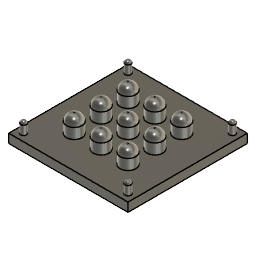
RUN 6 HOLLOW MAKER (Autodesk Fusion 360 design; units mm, degrees)
Autodesk Fusion 360 part; units mm, degrees
sketch "Sketch1" plane through (0, 0, 0) normal (0, 0, 1) x (1, 0, 0)
  line L0 (15, 15) -> (-15, 15)
  line L1 (-15, 15) -> (-15, -15)
  line L2 (-15, -15) -> (15, -15)
  line L3 (15, -15) -> (15, 15)
  line L4 (15, 15) -> (-15, -15) construction
  line L5 (-15, 15) -> (15, -15) construction
  line L6 (-20, 20) -> (-20, -20)
  line L7 (-20, -20) -> (20, -20)
  line L8 (20, -20) -> (20, 20)
  line L9 (20, 20) -> (-20, 20)
  circle A0 centre (0, 0) radius 2.625
  circle A1 centre (-9, -9) radius 2.625
  circle A2 centre (0, -9) radius 2.625
  circle A3 centre (9, -9) radius 2.625
  circle A4 centre (-9, 0) radius 2.625
  circle A5 centre (9, 0) radius 2.625
  circle A6 centre (-9, 9) radius 2.625
  circle A7 centre (0, 9) radius 2.625
  circle A8 centre (9, 9) radius 2.625
  line L10 (15, -15) -> (20, -20)
  line L11 (15, 15) -> (20, 20)
  line L12 (-15, 15) -> (-20, 20)
  line L13 (-15, -15) -> (-20, -20)
  circle A9 centre (-17.5, -17.5) radius 1
  circle A10 centre (17.5, -17.5) radius 1
  circle A11 centre (-17.5, 17.5) radius 1
  circle A12 centre (17.5, 17.5) radius 1
  dimension "d1" = 30
  dimension "d2" = 30
  dimension "d3" = 5
  dimension "d4" = 5.25
  dimension "d7" = 9
  dimension "d8" = 9
  dimension "d15" = 2
  dimension "d18" = 35
  dimension "d19" = 35
  constraint horizontal L0
  constraint perpendicular L0 L1
  constraint parallel L0 L2
  constraint parallel L1 L3
  constraint coincident L4 A0.centre
  constraint coincident L5 A0.centre
  constraint coincident A0.centre origin
  constraint perpendicular L10 L11
  constraint perpendicular L12 L13
  constraint midpoint L13 A9.centre
  measures "d1" distance of L1.end L2.end
  measures "d2" distance of L0.end L1.end
  measures "d4" diameter of A0
  measures "d15" diameter of A9
extrude "Extrude1" add sketch "Sketch1" against normal blind 3 contours L0 L1 L2 L3 | L3 L8 L10 L11 A10 A12 | L0 L9 L11 L12 A11 A12 | L1 L6 L12 L13 A9 A11 | L2 L7 L10 L13 A9 A10 | L11 A12 | L11 A12 | L12 A11 | L12 A11 | L10 A10 | L10 A10 | L13 A9 | L13 A9 | A0 | A1 | A2 | A3 | A4 | A5 | A6 | A7 | A8
extrude "Extrude2" add sketch "Sketch1" along normal blind 6 contours A0 | A1 | A2 | A3 | A4 | A5 | A6 | A7 | A8
fillet "Fillet1" radius 2.5 9 edges at (6.5526, -9.9492, 6) (6.5526, -0.9492, 6) (-2.4474, -0.9492, 6) (-2.4474, 8.0508, 6) (6.5526, 8.0508, 6) (-2.4474, -9.9492, 6) (-11.4474, -9.9492, 6) (-11.4474, -0.9492, 6) (-11.4474, 8.0508, 6)
extrude "Extrude3" add sketch "Sketch1" along normal blind 4 contours L11 A12 | L11 A12 | L12 A11 | L12 A11 | L10 A10 | L10 A10 | L13 A9 | L13 A9
fillet "Fillet2" radius 1 4 edges at (16.5677, 17.1384, 4) (16.5677, -17.8616, 4) (-18.4323, 17.1384, 4) (-18.4323, -17.8616, 4)
sketch "Sketch2" plane through (0, 0, -3) normal (0, 0, -1) x (1, 0, 0)
  line L0 (-20, -20) -> (20, -20)
  line L1 (20, -20) -> (20, 20)
  line L2 (20, 20) -> (-20, 20)
  line L3 (-20, 20) -> (-20, -20)
  line L4 (1, 1) -> (-1, 1)
  line L5 (-1, 1) -> (-1, -1)
  line L6 (-1, -1) -> (1, -1)
  line L7 (1, -1) -> (1, 1)
  line L8 (1, 1) -> (-1, -1) construction
  line L9 (-1, 1) -> (1, -1) construction
  line L10 (-7.6667, 1) -> (-9.6667, 1)
  line L11 (-7.6667, -1) -> (-7.6667, 1)
  line L12 (-9.6667, -1) -> (-7.6667, -1)
  line L13 (-9.6667, 1) -> (-9.6667, -1)
  line L14 (-3.3333, 1) -> (-5.3333, 1)
  line L15 (-3.3333, -1) -> (-3.3333, 1)
  line L16 (-5.3333, -1) -> (-3.3333, -1)
  line L17 (-5.3333, 1) -> (-5.3333, -1)
  line L18 (5.3333, 1) -> (3.3333, 1)
  line L19 (5.3333, -1) -> (5.3333, 1)
  line L20 (3.3333, -1) -> (5.3333, -1)
  line L21 (3.3333, 1) -> (3.3333, -1)
  line L22 (9.6667, 1) -> (7.6667, 1)
  line L23 (9.6667, -1) -> (9.6667, 1)
  line L24 (7.6667, -1) -> (9.6667, -1)
  line L25 (7.6667, 1) -> (7.6667, -1)
  line L26 (14, 1) -> (12, 1)
  line L27 (14, -1) -> (14, 1)
  line L28 (12, -1) -> (14, -1)
  line L29 (12, 1) -> (12, -1)
  dimension "d24" = 2
  dimension "d25" = 2
  dimension "d28" = 13
  dimension "d29" = 0
  constraint horizontal L4
  constraint perpendicular L4 L5
  constraint parallel L4 L6
  constraint parallel L5 L7
  constraint coincident L8 origin
  constraint coincident L9 origin
  measures "d24" distance of L5.end L6.end
  measures "d25" distance of L4.end L5.end
extrude "Extrude4" cut sketch "Sketch2" against normal blind 1 contours L4 L5 L6 L7 | L10 L11 L12 L13 | L14 L15 L16 L17 | L18 L19 L20 L21 | L22 L23 L24 L25 | L26 L27 L28 L29
